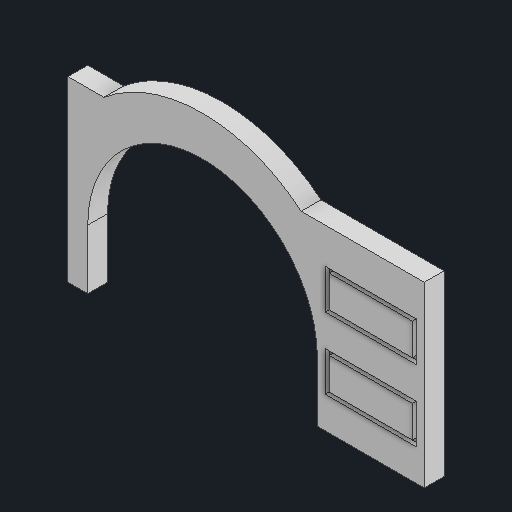
# Autodesk Inventor part: 7_1_6_tour_roue_avant_gauche
Saved by Autodesk Inventor 2026 (Build 300175000, 175)
## iProperties
Created: 2025-06-21
Part Number: 7_1_6_tour_roue_avant_gauche
Material: Generic
Document SubType Name: Modeling
Designer: remg9
Density: 1 g/cm^3
Appearance: Default
Author: remg9
Autodesk Inventor part; units mm, degrees
ref_plane "YZ Plane" through (0, 0, 0) normal (1, 0, 0) x (0, 1, 0)
ref_plane "XZ Plane" through (0, 0, 0) normal (0, 1, 0) x (-1, 0, 0)
ref_plane "XY Plane" through (0, 0, 0) normal (0, 0, 1) x (1, 0, 0)
sketch "Sketch1" plane through (0, 0, 0) normal (0, 0, 1) x (1, 0, 0)
  line L0 (0, 0) -> (-27, 0)
  line L1 (-31.0801, 45) -> (0, 45)
  line L2 (0, 45) -> (0, 0)
  line L3 (-27, 0) -> (-27, 15)
  line L4 (-27, 15) -> (-85, 15) construction
  line L5 (-85, 15) -> (-85, 0)
  line L6 (-85, 0) -> (-90, 0)
  line L7 (-90, 0) -> (-90, 45)
  line L8 (-90, 45) -> (-80.9199, 45)
  arc A0 (-27, 15) -> (-85, 15) centre (-56, 15) ccw
  arc A1 (-31.0801, 45) -> (-80.9199, 45) centre (-56, 15) ccw
  dimension "d0" = 45
  dimension "d1" = 15
  dimension "d2" = 29
  dimension "d3" = 10
  dimension "d4" = 5
  dimension "d5" = 27
  constraints: 18 end point, 4 point on circle, 3 perpendicular, 2 centre point, 2 collinear, 2 horizontal, 2 vertical, 1 coincident, 1 midpoint, 1 parallel
  measures "d0" distance of L1.end L0.start
  measures "d1" distance between parallel lines of L0 L4
  measures "d2" radius of A0
  measures "d3" radial gap between concentric circles of A1 A0
  measures "d4" distance between parallel lines of L7 L5
  measures "d5" distance between parallel lines of L2 L3
extrude "Extrusion1" add sketch "Sketch1" along normal blind 5
sketch "Sketch2" plane through (0, 0, 5) normal (0, 0, 1) x (1, 0, 0)
  line L0 (-25, 36) -> (-2, 36)
  line L1 (-2, 36) -> (-2, 26)
  line L2 (-2, 26) -> (-25, 26)
  line L3 (-25, 26) -> (-25, 36)
  line L4 (-24, 35) -> (-3, 35)
  line L5 (-3, 35) -> (-3, 27)
  line L6 (-3, 27) -> (-24, 27)
  line L7 (-24, 27) -> (-24, 35)
  line L8 (-25, 18) -> (-2, 18)
  line L9 (-2, 18) -> (-2, 8)
  line L10 (-2, 8) -> (-25, 8)
  line L11 (-25, 8) -> (-25, 18)
  line L12 (-24, 17) -> (-3, 17)
  line L13 (-3, 17) -> (-3, 9)
  line L14 (-3, 9) -> (-24, 9)
  line L15 (-24, 9) -> (-24, 17)
  line L16 (0, 0) -> (0, 45) projected
  line L17 (-27, 15) -> (-27, 0) projected
  line L18 (-27, 0) -> (0, 0) projected
  dimension "d8" = 2
  dimension "d9" = 2
  dimension "d10" = 1
  dimension "d11" = 1
  dimension "d12" = 1
  dimension "d13" = 1
  dimension "d14" = 1
  dimension "d15" = 1
  dimension "d16" = 8
  dimension "d17" = 10
  dimension "d18" = 8
  dimension "d19" = 10
  constraints: 32 end point, 8 parallel, 4 horizontal, 4 perpendicular, 4 point on line
  measures "d8" distance between parallel lines of L16 L9
  measures "d9" distance between parallel lines of L17 L11
  measures "d10" distance between parallel lines of L9 L13
  measures "d11" distance between parallel lines of L11 L15
  measures "d12" distance between parallel lines of L10 L14
  measures "d13" distance between parallel lines of L8 L12
  measures "d14" distance between parallel lines of L2 L6
  measures "d15" distance between parallel lines of L0 L4
  measures "d16" distance between parallel lines of L18 L10
  measures "d17" distance of L8.end L9.end
  measures "d18" distance between parallel lines of L2 L8
  measures "d19" distance of L0.end L1.end
extrude "Extrusion2" cut sketch "Sketch2" against normal blind 1
body "Solid1"
